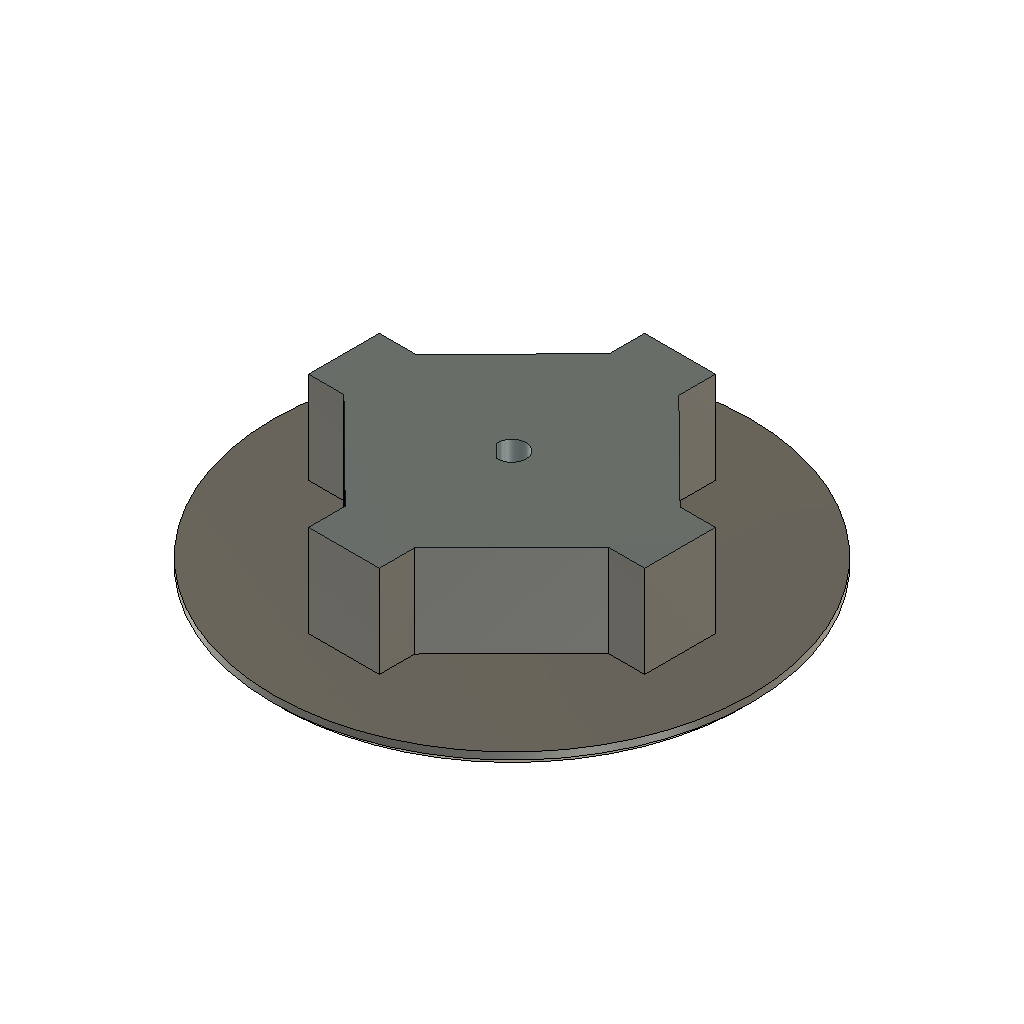
Airplane-2-wheel (Autodesk Fusion 360 design; units mm, degrees)
part number: 2026-11-19-01-23-22-793
Autodesk Fusion 360 part; units mm, degrees
sketch "Sketch1" plane through (0, 0, 0) normal (0, 0, 1) x (1, 0, 0)
  circle A0 centre (0, 0) radius 33.75
  dimension "d1" = 67.5
  constraint coincident A0.centre origin
  measures "d1" diameter of A0
extrude "Extrude1" add sketch "Sketch1" along normal blind 2
sketch "Sketch2" plane through (0, 0, 2) normal (0, 0, 1) x (-1, 0, 0)
  circle A0 centre (0, 0) radius 33.75
  line L0 (-5, -23.75) -> (5, -23.75)
  line L1 (5, -23.75) -> (5, 23.75)
  line L2 (5, 23.75) -> (-5, 23.75)
  line L3 (-5, 23.75) -> (-5, -23.75)
  line L4 (-5, -23.75) -> (5, 23.75) construction
  line L5 (5, -23.75) -> (-5, 23.75) construction
  line L6 (23.75, -5) -> (23.75, 5)
  line L7 (23.75, -5) -> (-23.75, 5) construction
  line L8 (-23.75, 5) -> (-23.75, -5)
  line L9 (23.75, 5) -> (-23.75, -5) construction
  line L10 (23.75, 5) -> (-23.75, 5)
  line L11 (-23.75, -5) -> (23.75, -5)
  line L12 (5, -18.75) -> (18.75, -4.8219)
  line L13 (18.75, 5) -> (4.8219, 18.75)
  line L14 (-5, 18.75) -> (-18.75, 4.8219)
  line L15 (-18.75, -5) -> (-4.8219, -18.75)
  dimension "d4" = 10
  dimension "d5" = 47.5
  dimension "d6" = 10
  dimension "d7" = 47.5
  dimension "d8" = 5
  dimension "d9" = 5
  dimension "d11" = 360
  constraint horizontal L0
  constraint perpendicular L0 L1
  constraint parallel L0 L2
  constraint parallel L1 L3
  constraint coincident L4 A0.centre
  constraint coincident L5 A0.centre
  constraint coincident A0.centre origin
  constraint perpendicular L6 L10
  constraint parallel L6 L8
  constraint parallel L10 L11
  constraint coincident A0.centre L7
  constraint coincident A0.centre L9
  constraint coincident L1 L12.start
  constraint horizontal L11
  measures "d4" distance of L1.end L2.end
  measures "d5" distance of L0.end L1.end
  measures "d6" distance of L8.end L7.end
  measures "d7" distance of L6.end L7.end
  measures "d8" distance of L0.end L12.start
  measures "d9" horizontal distance of L6.start L12.end
extrude "Extrude2" add sketch "Sketch2" along normal blind 13 contours L0 L1 L3 L11 | L3 L11 L15 | L1 L11 L12 | L3 L8 L10 L11 | L1 L3 L10 L11 | L1 L6 L10 L11 | L3 L10 L14 | L1 L2 L3 L10 | L1 L10 L13
sketch "Sketch3" plane through (0, 0, 15) normal (0, 0, 1) x (-1, 0, 0)
  line L0 (-18.75, -5) -> (-5, -18.5742)
  line L1 (-5, -18.5742) -> (-5, -23.75)
  line L2 (-5, -23.75) -> (5, -23.75)
  line L3 (5, -23.75) -> (5, -18.75)
  line L4 (5, -18.75) -> (18.5742, -5)
  line L5 (18.5742, -5) -> (23.75, -5)
  line L6 (23.75, -5) -> (23.75, 5)
  line L7 (23.75, 5) -> (18.75, 5)
  line L8 (18.75, 5) -> (5, 18.5742)
  line L9 (5, 18.5742) -> (5, 23.75)
  line L10 (5, 23.75) -> (-5, 23.75)
  line L11 (-5, 23.75) -> (-5, 18.75)
  line L12 (-5, 18.75) -> (-18.5742, 5)
  line L13 (-18.5742, 5) -> (-23.75, 5)
  line L14 (-23.75, 5) -> (-23.75, -5)
  line L15 (-23.75, -5) -> (-18.75, -5)
  arc A0 (0.1915, 1.9908) -> (1.9908, 0.1915) centre (0, 0) ccw
  line L16 (0.1915, 1.9908) -> (1.9908, 0.1915)
  dimension "d14" = 2
  dimension "d15" = 1.5432
  measures "d14" radius of A0
  measures "d15" distance of A0.centre L16
extrude "Extrude3" cut sketch "Sketch3" against normal blind 13 contours A0 L16
chamfer "Chamfer1" distance 1 angle 45 1 edges at (-31.466, -12.2045, 0) tangent chain off
sketch "Sketch4" plane through (-11.7541, -11.9064, 0) normal (-0.702542, -0.711643, 0) x (0.711643, -0.702542, 0)
  line L0 (-9.8306, 2) -> (9.4909, 2)
  line L1 (9.4909, 2) -> (9.4909, 15)
  line L2 (9.4909, 15) -> (-9.8306, 15)
  line L3 (-9.8306, 15) -> (-9.8306, 2)
  circle A0 centre (-0.1698, 6.5) radius 4.5
  line L4 (-0.1698, 6.5) -> (-0.1698, 15)
  dimension "d19" = 9
  constraint tangent L0 A0
  constraint coincident A0.centre L4.start
  constraint coincident L2 L4.end
  constraint perpendicular L2 L4
  constraint midpoint L2 L4.end
  measures "d19" diameter of A0
extrude "Extrude4" cut sketch "Sketch4" against normal blind 10 contours A0
sketch "Sketch5" plane through (-4.7287, -4.79, 0) normal (-0.702542, -0.711643, 0) x (0.711643, -0.702542, 0)
  circle A0 centre (-0.1698, 6.5) radius 4.5
  circle A1 centre (-0.1698, 6.5) radius 1.85
  dimension "d22" = 3.7
  constraint concentric A0 A1
  measures "d22" diameter of A1
extrude "Extrude5" cut sketch "Sketch5" against normal blind 7 contours A1
sketch "Sketch6" plane through (0, 0, 15) normal (0, 0, 1) x (-1, 0, 0)
  line L0 (0.1915, 1.9908) -> (1.9908, 0.1915)
  arc A0 (0.1915, 1.9908) -> (1.9908, 0.1915) centre (0, 0) ccw
  line L1 (-18.75, -5) -> (-5, -18.5742)
  line L2 (-5, -18.5742) -> (-5, -23.75)
  line L3 (-5, -23.75) -> (5, -23.75)
  line L4 (5, -23.75) -> (5, -18.75)
  line L5 (5, -18.75) -> (18.5742, -5)
  line L6 (18.5742, -5) -> (23.75, -5)
  line L7 (23.75, -5) -> (23.75, 5)
  line L8 (23.75, 5) -> (18.75, 5)
  line L9 (18.75, 5) -> (5, 18.5742)
  line L10 (5, 18.5742) -> (5, 23.75)
  line L11 (5, 23.75) -> (-5, 23.75)
  line L12 (-5, 23.75) -> (-5, 18.75)
  line L13 (-5, 18.75) -> (-18.5742, 5)
  line L14 (-18.5742, 5) -> (-23.75, 5)
  line L15 (-23.75, 5) -> (-23.75, -5)
  line L16 (-23.75, -5) -> (-18.75, -5)
equation "d9 = d8"
